Autodesk Fusion 360 part; units mm, degrees
(part 4 of 7)
sketch "Rear slot mouth sketch (2)" plane through (0, 0, 35) normal (0, 0, 1) x (1, 0, 0) in component "Vertical rail 1 - nominal 2020 slot-6 envelope"
  line L0 (117, 2) -> (123, 2)
  line L1 (123, 2) -> (123, 238)
  line L2 (123, 238) -> (117, 238)
  line L3 (117, 238) -> (117, 2)
  dimension "d1401" = 117
  dimension "d1402" = 2
  dimension "d1403" = 6
  dimension "d1404" = 236
  constraint horizontal L0
  constraint vertical L1
  constraint horizontal L2
  constraint vertical L3
  measures "d1401" horizontal distance of origin L0.start
  measures "d1402" vertical distance of origin L0.start
  measures "d1403" horizontal distance of L0.start L0.end
  measures "d1404" vertical distance of L0.end L1.end
extrude "Rear slot mouth'" cut sketch "Rear slot mouth sketch (2)" against normal blind 1.8 bodies 10 in component "Vertical rail 1 - nominal 2020 slot-6 envelope"
ref_plane "WorkPlane5" through (0, 0, 33.2) normal (0, 0, 1) x (1, 0, 0) in component "Vertical rail 1 - nominal 2020 slot-6 envelope"
sketch "Rear T nut cavity sketch (2)" plane through (0, 0, 33.2) normal (0, 0, 1) x (1, 0, 0) in component "Vertical rail 1 - nominal 2020 slot-6 envelope"
  line L0 (115, 2) -> (125, 2)
  line L1 (125, 2) -> (125, 238)
  line L2 (125, 238) -> (115, 238)
  line L3 (115, 238) -> (115, 2)
  dimension "d1409" = 115
  dimension "d1410" = 2
  dimension "d1411" = 10
  dimension "d1412" = 236
  constraint horizontal L0
  constraint vertical L1
  constraint horizontal L2
  constraint vertical L3
  measures "d1409" horizontal distance of origin L0.start
  measures "d1410" vertical distance of origin L0.start
  measures "d1411" horizontal distance of L0.start L0.end
  measures "d1412" vertical distance of L0.end L1.end
extrude "Rear T nut cavity'" cut sketch "Rear T nut cavity sketch (2)" against normal blind 4.2 bodies 10 in component "Vertical rail 1 - nominal 2020 slot-6 envelope"
ref_plane "WorkPlane4" through (0, 0, 35) normal (0, 0, 1) x (1, 0, 0) in component "Vertical rail 2 - nominal 2020 slot-6 envelope"
sketch "Rear slot mouth sketch (3)" plane through (0, 0, 35) normal (0, 0, 1) x (1, 0, 0) in component "Vertical rail 2 - nominal 2020 slot-6 envelope"
  line L0 (225, 2) -> (231, 2)
  line L1 (231, 2) -> (231, 238)
  line L2 (231, 238) -> (225, 238)
  line L3 (225, 238) -> (225, 2)
  dimension "d1417" = 225
  dimension "d1418" = 2
  dimension "d1419" = 6
  dimension "d1420" = 236
  constraint horizontal L0
  constraint vertical L1
  constraint horizontal L2
  constraint vertical L3
  measures "d1417" horizontal distance of origin L0.start
  measures "d1418" vertical distance of origin L0.start
  measures "d1419" horizontal distance of L0.start L0.end
  measures "d1420" vertical distance of L0.end L1.end
extrude "Rear slot mouth''" cut sketch "Rear slot mouth sketch (3)" against normal blind 1.8 bodies 11 in component "Vertical rail 2 - nominal 2020 slot-6 envelope"
ref_plane "WorkPlane5" through (0, 0, 33.2) normal (0, 0, 1) x (1, 0, 0) in component "Vertical rail 2 - nominal 2020 slot-6 envelope"
sketch "Rear T nut cavity sketch (3)" plane through (0, 0, 33.2) normal (0, 0, 1) x (1, 0, 0) in component "Vertical rail 2 - nominal 2020 slot-6 envelope"
  line L0 (223, 2) -> (233, 2)
  line L1 (233, 2) -> (233, 238)
  line L2 (233, 238) -> (223, 238)
  line L3 (223, 238) -> (223, 2)
  dimension "d1425" = 223
  dimension "d1426" = 2
  dimension "d1427" = 10
  dimension "d1428" = 236
  constraint horizontal L0
  constraint vertical L1
  constraint horizontal L2
  constraint vertical L3
  measures "d1425" horizontal distance of origin L0.start
  measures "d1426" vertical distance of origin L0.start
  measures "d1427" horizontal distance of L0.start L0.end
  measures "d1428" vertical distance of L0.end L1.end
extrude "Rear T nut cavity''" cut sketch "Rear T nut cavity sketch (3)" against normal blind 4.2 bodies 11 in component "Vertical rail 2 - nominal 2020 slot-6 envelope"
ref_plane "WorkPlane4" through (0, 0, 35) normal (0, 0, 1) x (1, 0, 0) in component "Horizontal tie 00 - nominal 2020 slot-6 envelope"
sketch "Rear slot mouth sketch (4)" plane through (0, 0, 35) normal (0, 0, 1) x (1, 0, 0) in component "Horizontal tie 00 - nominal 2020 slot-6 envelope"
  line L0 (22, 9) -> (110, 9)
  line L1 (110, 9) -> (110, 15)
  line L2 (110, 15) -> (22, 15)
  line L3 (22, 15) -> (22, 9)
  dimension "d1433" = 22
  dimension "d1434" = 9
  dimension "d1435" = 88
  dimension "d1436" = 6
  constraint horizontal L0
  constraint vertical L1
  constraint horizontal L2
  constraint vertical L3
  measures "d1433" horizontal distance of origin L0.start
  measures "d1434" vertical distance of origin L0.start
  measures "d1435" horizontal distance of L0.start L0.end
  measures "d1436" vertical distance of L0.end L1.end
extrude "Rear slot mouth'''" cut sketch "Rear slot mouth sketch (4)" against normal blind 1.8 bodies 12 in component "Horizontal tie 00 - nominal 2020 slot-6 envelope"
ref_plane "WorkPlane5" through (0, 0, 33.2) normal (0, 0, 1) x (1, 0, 0) in component "Horizontal tie 00 - nominal 2020 slot-6 envelope"
sketch "Rear T nut cavity sketch (4)" plane through (0, 0, 33.2) normal (0, 0, 1) x (1, 0, 0) in component "Horizontal tie 00 - nominal 2020 slot-6 envelope"
  line L0 (22, 7) -> (110, 7)
  line L1 (110, 7) -> (110, 17)
  line L2 (110, 17) -> (22, 17)
  line L3 (22, 17) -> (22, 7)
  dimension "d1441" = 22
  dimension "d1442" = 7
  dimension "d1443" = 88
  dimension "d1444" = 10
  constraint horizontal L0
  constraint vertical L1
  constraint horizontal L2
  constraint vertical L3
  measures "d1441" horizontal distance of origin L0.start
  measures "d1442" vertical distance of origin L0.start
  measures "d1443" horizontal distance of L0.start L0.end
  measures "d1444" vertical distance of L0.end L1.end
extrude "Rear T nut cavity'''" cut sketch "Rear T nut cavity sketch (4)" against normal blind 4.2 bodies 12 in component "Horizontal tie 00 - nominal 2020 slot-6 envelope"
ref_plane "WorkPlane4" through (0, 0, 35) normal (0, 0, 1) x (1, 0, 0) in component "Horizontal tie 10 - nominal 2020 slot-6 envelope"
sketch "Rear slot mouth sketch (5)" plane through (0, 0, 35) normal (0, 0, 1) x (1, 0, 0) in component "Horizontal tie 10 - nominal 2020 slot-6 envelope"
  line L0 (130, 9) -> (218, 9)
  line L1 (218, 9) -> (218, 15)
  line L2 (218, 15) -> (130, 15)
  line L3 (130, 15) -> (130, 9)
  dimension "d1449" = 130
  dimension "d1450" = 9
  dimension "d1451" = 88
  dimension "d1452" = 6
  constraint horizontal L0
  constraint vertical L1
  constraint horizontal L2
  constraint vertical L3
  measures "d1449" horizontal distance of origin L0.start
  measures "d1450" vertical distance of origin L0.start
  measures "d1451" horizontal distance of L0.start L0.end
  measures "d1452" vertical distance of L0.end L1.end
extrude "Rear slot mouth''''" cut sketch "Rear slot mouth sketch (5)" against normal blind 1.8 bodies 13 in component "Horizontal tie 10 - nominal 2020 slot-6 envelope"
ref_plane "WorkPlane5" through (0, 0, 33.2) normal (0, 0, 1) x (1, 0, 0) in component "Horizontal tie 10 - nominal 2020 slot-6 envelope"
sketch "Rear T nut cavity sketch (5)" plane through (0, 0, 33.2) normal (0, 0, 1) x (1, 0, 0) in component "Horizontal tie 10 - nominal 2020 slot-6 envelope"
  line L0 (130, 7) -> (218, 7)
  line L1 (218, 7) -> (218, 17)
  line L2 (218, 17) -> (130, 17)
  line L3 (130, 17) -> (130, 7)
  dimension "d1457" = 130
  dimension "d1458" = 7
  dimension "d1459" = 88
  dimension "d1460" = 10
  constraint horizontal L0
  constraint vertical L1
  constraint horizontal L2
  constraint vertical L3
  measures "d1457" horizontal distance of origin L0.start
  measures "d1458" vertical distance of origin L0.start
  measures "d1459" horizontal distance of L0.start L0.end
  measures "d1460" vertical distance of L0.end L1.end
extrude "Rear T nut cavity''''" cut sketch "Rear T nut cavity sketch (5)" against normal blind 4.2 bodies 13 in component "Horizontal tie 10 - nominal 2020 slot-6 envelope"
ref_plane "WorkPlane1" through (0, 0, 35) normal (0, 0, 1) x (1, 0, 0) in component "METAL rear splice plate 00"
sketch "Rear rail join plate sketch" plane through (0, 0, 35) normal (0, 0, 1) x (1, 0, 0) in component "METAL rear splice plate 00"
  line L0 (4, 4) -> (40, 4)
  line L1 (40, 4) -> (40, 20)
  line L2 (40, 20) -> (4, 20)
  line L3 (4, 20) -> (4, 4)
  dimension "d1465" = 4
  dimension "d1466" = 4
  dimension "d1467" = 36
  dimension "d1468" = 16
  constraint horizontal L0
  constraint vertical L1
  constraint horizontal L2
  constraint vertical L3
  measures "d1465" horizontal distance of origin L0.start
  measures "d1466" vertical distance of origin L0.start
  measures "d1467" horizontal distance of L0.start L0.end
  measures "d1468" vertical distance of L0.end L1.end
extrude "Rear rail join plate" add sketch "Rear rail join plate sketch" along normal blind 3 separate body makes body 61 in component "METAL rear splice plate 00"
ref_plane "WorkPlane2" through (0, 0, 35) normal (0, 0, 1) x (1, 0, 0) in component "METAL rear splice plate 00"
sketch "M5 clearance sketch (10)" plane through (0, 0, 35) normal (0, 0, 1) x (1, 0, 0) in component "METAL rear splice plate 00"
  circle A0 centre (12, 12) radius 2.75
  dimension "d1473" = 12
  dimension "d1474" = 12
  dimension "d1475" = 5.5
  measures "d1473" horizontal distance of origin A0.centre
  measures "d1474" vertical distance of origin A0.centre
  measures "d1475" diameter of A0
extrude "M5 clearance'''''''''" cut sketch "M5 clearance sketch (10)" along normal blind 3 bodies 61 in component "METAL rear splice plate 00"
ref_plane "WorkPlane1" through (0, 0, 38) normal (0, 0, 1) x (1, 0, 0) in component "REFERENCE rear join screw 000"
sketch "Nominal head sketch" plane through (0, 0, 38) normal (0, 0, 1) x (1, 0, 0) in component "REFERENCE rear join screw 000"
  circle A0 centre (12, 12) radius 4.75
  dimension "d1480" = 12
  dimension "d1481" = 12
  dimension "d1482" = 9.5
  measures "d1480" horizontal distance of origin A0.centre
  measures "d1481" vertical distance of origin A0.centre
  measures "d1482" diameter of A0
extrude "Nominal head" add sketch "Nominal head sketch" along normal blind 3 separate body makes body 62 in component "REFERENCE rear join screw 000"
ref_plane "WorkPlane2" through (0, 0, 38) normal (0, 0, 1) x (1, 0, 0) in component "REFERENCE rear join screw 000"
sketch "M5x8 nominal shank sketch" plane through (0, 0, 38) normal (0, 0, 1) x (1, 0, 0) in component "REFERENCE rear join screw 000"
  circle A0 centre (12, 12) radius 2.5
  dimension "d1487" = 12
  dimension "d1488" = 12
  dimension "d1489" = 5
  measures "d1487" horizontal distance of origin A0.centre
  measures "d1488" vertical distance of origin A0.centre
  measures "d1489" diameter of A0
extrude "M5x8 nominal shank" add sketch "M5x8 nominal shank sketch" against normal blind 8 bodies 62 in component "REFERENCE rear join screw 000"
ref_plane "WorkPlane1" through (0, 0, 29) normal (0, 0, 1) x (1, 0, 0) in component "REFERENCE rear T nut 000"
sketch "T nut envelope sketch (10)" plane through (0, 0, 29) normal (0, 0, 1) x (1, 0, 0) in component "REFERENCE rear T nut 000"
  line L0 (7.2, 7.2) -> (16.8, 7.2)
  line L1 (16.8, 7.2) -> (16.8, 16.8)
  line L2 (16.8, 16.8) -> (7.2, 16.8)
  line L3 (7.2, 16.8) -> (7.2, 7.2)
  dimension "d1494" = 7.2
  dimension "d1495" = 7.2
  dimension "d1496" = 9.6
  dimension "d1497" = 9.6
  constraint horizontal L0
  constraint vertical L1
  constraint horizontal L2
  constraint vertical L3
  measures "d1494" horizontal distance of origin L0.start
  measures "d1495" vertical distance of origin L0.start
  measures "d1496" horizontal distance of L0.start L0.end
  measures "d1497" vertical distance of L0.end L1.end
extrude "T nut envelope'''''''''" add sketch "T nut envelope sketch (10)" along normal blind 4 separate body makes body 63 in component "REFERENCE rear T nut 000"
ref_plane "WorkPlane2" through (0, 0, 29) normal (0, 0, 1) x (1, 0, 0) in component "REFERENCE rear T nut 000"
sketch "Thread envelope sketch (10)" plane through (0, 0, 29) normal (0, 0, 1) x (1, 0, 0) in component "REFERENCE rear T nut 000"
  circle A0 centre (12, 12) radius 2.6
  dimension "d1502" = 12
  dimension "d1503" = 12
  dimension "d1504" = 5.2
  measures "d1502" horizontal distance of origin A0.centre
  measures "d1503" vertical distance of origin A0.centre
  measures "d1504" diameter of A0
extrude "Thread envelope'''''''''" cut sketch "Thread envelope sketch (10)" along normal blind 4 bodies 62 in component "REFERENCE rear join screw 000"
extrude "Extrude2'''''''''" cut sketch "Thread envelope sketch (10)" along normal blind 4 bodies 63 in component "REFERENCE rear T nut 000"
ref_plane "WorkPlane3" through (0, 0, 35) normal (0, 0, 1) x (1, 0, 0) in component "METAL rear splice plate 00"
sketch "M5 clearance sketch (1)" plane through (0, 0, 35) normal (0, 0, 1) x (1, 0, 0) in component "METAL rear splice plate 00"
  circle A0 centre (32, 12) radius 2.75
  dimension "d1511" = 32
  dimension "d1512" = 12
  dimension "d1513" = 5.5
  measures "d1511" horizontal distance of origin A0.centre
  measures "d1512" vertical distance of origin A0.centre
  measures "d1513" diameter of A0
extrude "M5 clearance (1)" cut sketch "M5 clearance sketch (1)" along normal blind 3 bodies 61 in component "METAL rear splice plate 00"
ref_plane "WorkPlane1" through (0, 0, 38) normal (0, 0, 1) x (1, 0, 0) in component "REFERENCE rear join screw 001"
sketch "Nominal head sketch (2)" plane through (0, 0, 38) normal (0, 0, 1) x (1, 0, 0) in component "REFERENCE rear join screw 001"
  circle A0 centre (32, 12) radius 4.75
  dimension "d1518" = 32
  dimension "d1519" = 12
  dimension "d1520" = 9.5
  measures "d1518" horizontal distance of origin A0.centre
  measures "d1519" vertical distance of origin A0.centre
  measures "d1520" diameter of A0
extrude "Nominal head'" add sketch "Nominal head sketch (2)" along normal blind 3 separate body makes body 64 in component "REFERENCE rear join screw 001"
ref_plane "WorkPlane2" through (0, 0, 38) normal (0, 0, 1) x (1, 0, 0) in component "REFERENCE rear join screw 001"
sketch "M5x8 nominal shank sketch (2)" plane through (0, 0, 38) normal (0, 0, 1) x (1, 0, 0) in component "REFERENCE rear join screw 001"
  circle A0 centre (32, 12) radius 2.5
  dimension "d1525" = 32
  dimension "d1526" = 12
  dimension "d1527" = 5
  measures "d1525" horizontal distance of origin A0.centre
  measures "d1526" vertical distance of origin A0.centre
  measures "d1527" diameter of A0
extrude "M5x8 nominal shank'" add sketch "M5x8 nominal shank sketch (2)" against normal blind 8 bodies 64 in component "REFERENCE rear join screw 001"
ref_plane "WorkPlane1" through (0, 0, 29) normal (0, 0, 1) x (1, 0, 0) in component "REFERENCE rear T nut 001"
sketch "T nut envelope sketch (11)" plane through (0, 0, 29) normal (0, 0, 1) x (1, 0, 0) in component "REFERENCE rear T nut 001"
  line L0 (27.2, 7.2) -> (36.8, 7.2)
  line L1 (36.8, 7.2) -> (36.8, 16.8)
  line L2 (36.8, 16.8) -> (27.2, 16.8)
  line L3 (27.2, 16.8) -> (27.2, 7.2)
  dimension "d1532" = 27.2
  dimension "d1533" = 7.2
  dimension "d1534" = 9.6
  dimension "d1535" = 9.6
  constraint horizontal L0
  constraint vertical L1
  constraint horizontal L2
  constraint vertical L3
  measures "d1532" horizontal distance of origin L0.start
  measures "d1533" vertical distance of origin L0.start
  measures "d1534" horizontal distance of L0.start L0.end
  measures "d1535" vertical distance of L0.end L1.end
extrude "T nut envelope''''''''''" add sketch "T nut envelope sketch (11)" along normal blind 4 separate body makes body 65 in component "REFERENCE rear T nut 001"
ref_plane "WorkPlane2" through (0, 0, 29) normal (0, 0, 1) x (1, 0, 0) in component "REFERENCE rear T nut 001"
sketch "Thread envelope sketch (11)" plane through (0, 0, 29) normal (0, 0, 1) x (1, 0, 0) in component "REFERENCE rear T nut 001"
  circle A0 centre (32, 12) radius 2.6
  dimension "d1540" = 32
  dimension "d1541" = 12
  dimension "d1542" = 5.2
  measures "d1540" horizontal distance of origin A0.centre
  measures "d1541" vertical distance of origin A0.centre
  measures "d1542" diameter of A0
extrude "Thread envelope''''''''''" cut sketch "Thread envelope sketch (11)" along normal blind 4 bodies 64 in component "REFERENCE rear join screw 001"
extrude "Extrude2''''''''''" cut sketch "Thread envelope sketch (11)" along normal blind 4 bodies 65 in component "REFERENCE rear T nut 001"
ref_plane "WorkPlane1" through (0, 0, 35) normal (0, 0, 1) x (1, 0, 0) in component "METAL rear splice plate 10"
sketch "Rear rail join plate sketch (2)" plane through (0, 0, 35) normal (0, 0, 1) x (1, 0, 0) in component "METAL rear splice plate 10"
  line L0 (92, 4) -> (148, 4)
  line L1 (148, 4) -> (148, 20)
  line L2 (148, 20) -> (92, 20)
  line L3 (92, 20) -> (92, 4)
  dimension "d1549" = 92
  dimension "d1550" = 4
  dimension "d1551" = 56
  dimension "d1552" = 16
  constraint horizontal L0
  constraint vertical L1
  constraint horizontal L2
  constraint vertical L3
  measures "d1549" horizontal distance of origin L0.start
  measures "d1550" vertical distance of origin L0.start
  measures "d1551" horizontal distance of L0.start L0.end
  measures "d1552" vertical distance of L0.end L1.end
extrude "Rear rail join plate'" add sketch "Rear rail join plate sketch (2)" along normal blind 3 separate body makes body 66 in component "METAL rear splice plate 10"
ref_plane "WorkPlane2" through (0, 0, 35) normal (0, 0, 1) x (1, 0, 0) in component "METAL rear splice plate 10"
sketch "M5 clearance sketch (11)" plane through (0, 0, 35) normal (0, 0, 1) x (1, 0, 0) in component "METAL rear splice plate 10"
  circle A0 centre (100, 12) radius 2.75
  dimension "d1557" = 100
  dimension "d1558" = 12
  dimension "d1559" = 5.5
  measures "d1557" horizontal distance of origin A0.centre
  measures "d1558" vertical distance of origin A0.centre
  measures "d1559" diameter of A0
extrude "M5 clearance''''''''''" cut sketch "M5 clearance sketch (11)" along normal blind 3 bodies 66 in component "METAL rear splice plate 10"
ref_plane "WorkPlane1" through (0, 0, 38) normal (0, 0, 1) x (1, 0, 0) in component "REFERENCE rear join screw 100"
sketch "Nominal head sketch (3)" plane through (0, 0, 38) normal (0, 0, 1) x (1, 0, 0) in component "REFERENCE rear join screw 100"
  circle A0 centre (100, 12) radius 4.75
  dimension "d1564" = 100
  dimension "d1565" = 12
  dimension "d1566" = 9.5
  measures "d1564" horizontal distance of origin A0.centre
  measures "d1565" vertical distance of origin A0.centre
  measures "d1566" diameter of A0
extrude "Nominal head''" add sketch "Nominal head sketch (3)" along normal blind 3 separate body makes body 67 in component "REFERENCE rear join screw 100"
ref_plane "WorkPlane2" through (0, 0, 38) normal (0, 0, 1) x (1, 0, 0) in component "REFERENCE rear join screw 100"
sketch "M5x8 nominal shank sketch (3)" plane through (0, 0, 38) normal (0, 0, 1) x (1, 0, 0) in component "REFERENCE rear join screw 100"
  circle A0 centre (100, 12) radius 2.5
  dimension "d1571" = 100
  dimension "d1572" = 12
  dimension "d1573" = 5
  measures "d1571" horizontal distance of origin A0.centre
  measures "d1572" vertical distance of origin A0.centre
  measures "d1573" diameter of A0
extrude "M5x8 nominal shank''" add sketch "M5x8 nominal shank sketch (3)" against normal blind 8 bodies 67 in component "REFERENCE rear join screw 100"
ref_plane "WorkPlane1" through (0, 0, 29) normal (0, 0, 1) x (1, 0, 0) in component "REFERENCE rear T nut 100"
sketch "T nut envelope sketch (12)" plane through (0, 0, 29) normal (0, 0, 1) x (1, 0, 0) in component "REFERENCE rear T nut 100"
  line L0 (95.2, 7.2) -> (104.8, 7.2)
  line L1 (104.8, 7.2) -> (104.8, 16.8)
  line L2 (104.8, 16.8) -> (95.2, 16.8)
  line L3 (95.2, 16.8) -> (95.2, 7.2)
  dimension "d1578" = 95.2
  dimension "d1579" = 7.2
  dimension "d1580" = 9.6
  dimension "d1581" = 9.6
  constraint horizontal L0
  constraint vertical L1
  constraint horizontal L2
  constraint vertical L3
  measures "d1578" horizontal distance of origin L0.start
  measures "d1579" vertical distance of origin L0.start
  measures "d1580" horizontal distance of L0.start L0.end
  measures "d1581" vertical distance of L0.end L1.end
extrude "T nut envelope'''''''''''" add sketch "T nut envelope sketch (12)" along normal blind 4 separate body makes body 68 in component "REFERENCE rear T nut 100"
ref_plane "WorkPlane2" through (0, 0, 29) normal (0, 0, 1) x (1, 0, 0) in component "REFERENCE rear T nut 100"
sketch "Thread envelope sketch (12)" plane through (0, 0, 29) normal (0, 0, 1) x (1, 0, 0) in component "REFERENCE rear T nut 100"
  circle A0 centre (100, 12) radius 2.6
  dimension "d1586" = 100
  dimension "d1587" = 12
  dimension "d1588" = 5.2
  measures "d1586" horizontal distance of origin A0.centre
  measures "d1587" vertical distance of origin A0.centre
  measures "d1588" diameter of A0
extrude "Thread envelope'''''''''''" cut sketch "Thread envelope sketch (12)" along normal blind 4 bodies 67 in component "REFERENCE rear join screw 100"
extrude "Extrude2'''''''''''" cut sketch "Thread envelope sketch (12)" along normal blind 4 bodies 68 in component "REFERENCE rear T nut 100"
ref_plane "WorkPlane3" through (0, 0, 35) normal (0, 0, 1) x (1, 0, 0) in component "METAL rear splice plate 10"
sketch "M5 clearance sketch (1) (2)" plane through (0, 0, 35) normal (0, 0, 1) x (1, 0, 0) in component "METAL rear splice plate 10"
  circle A0 centre (120, 12) radius 2.75
  dimension "d1595" = 120
  dimension "d1596" = 12
  dimension "d1597" = 5.5
  measures "d1595" horizontal distance of origin A0.centre
  measures "d1596" vertical distance of origin A0.centre
  measures "d1597" diameter of A0
extrude "M5 clearance (1)'" cut sketch "M5 clearance sketch (1) (2)" along normal blind 3 bodies 66 in component "METAL rear splice plate 10"
ref_plane "WorkPlane1" through (0, 0, 38) normal (0, 0, 1) x (1, 0, 0) in component "REFERENCE rear join screw 101"
sketch "Nominal head sketch (4)" plane through (0, 0, 38) normal (0, 0, 1) x (1, 0, 0) in component "REFERENCE rear join screw 101"
  circle A0 centre (120, 12) radius 4.75
  dimension "d1602" = 120
  dimension "d1603" = 12
  dimension "d1604" = 9.5
  measures "d1602" horizontal distance of origin A0.centre
  measures "d1603" vertical distance of origin A0.centre
  measures "d1604" diameter of A0
extrude "Nominal head'''" add sketch "Nominal head sketch (4)" along normal blind 3 separate body makes body 69 in component "REFERENCE rear join screw 101"
ref_plane "WorkPlane2" through (0, 0, 38) normal (0, 0, 1) x (1, 0, 0) in component "REFERENCE rear join screw 101"
sketch "M5x8 nominal shank sketch (4)" plane through (0, 0, 38) normal (0, 0, 1) x (1, 0, 0) in component "REFERENCE rear join screw 101"
  circle A0 centre (120, 12) radius 2.5
  dimension "d1609" = 120
  dimension "d1610" = 12
  dimension "d1611" = 5
  measures "d1609" horizontal distance of origin A0.centre
  measures "d1610" vertical distance of origin A0.centre
  measures "d1611" diameter of A0
extrude "M5x8 nominal shank'''" add sketch "M5x8 nominal shank sketch (4)" against normal blind 8 bodies 69 in component "REFERENCE rear join screw 101"
ref_plane "WorkPlane1" through (0, 0, 29) normal (0, 0, 1) x (1, 0, 0) in component "REFERENCE rear T nut 101"
sketch "T nut envelope sketch (13)" plane through (0, 0, 29) normal (0, 0, 1) x (1, 0, 0) in component "REFERENCE rear T nut 101"
  line L0 (115.2, 7.2) -> (124.8, 7.2)
  line L1 (124.8, 7.2) -> (124.8, 16.8)
  line L2 (124.8, 16.8) -> (115.2, 16.8)
  line L3 (115.2, 16.8) -> (115.2, 7.2)
  dimension "d1616" = 115.2
  dimension "d1617" = 7.2
  dimension "d1618" = 9.6
  dimension "d1619" = 9.6
  constraint horizontal L0
  constraint vertical L1
  constraint horizontal L2
  constraint vertical L3
  measures "d1616" horizontal distance of origin L0.start
  measures "d1617" vertical distance of origin L0.start
  measures "d1618" horizontal distance of L0.start L0.end
  measures "d1619" vertical distance of L0.end L1.end
extrude "T nut envelope''''''''''''" add sketch "T nut envelope sketch (13)" along normal blind 4 separate body makes body 70 in component "REFERENCE rear T nut 101"
ref_plane "WorkPlane2" through (0, 0, 29) normal (0, 0, 1) x (1, 0, 0) in component "REFERENCE rear T nut 101"
sketch "Thread envelope sketch (13)" plane through (0, 0, 29) normal (0, 0, 1) x (1, 0, 0) in component "REFERENCE rear T nut 101"
  circle A0 centre (120, 12) radius 2.6
  dimension "d1624" = 120
  dimension "d1625" = 12
  dimension "d1626" = 5.2
  measures "d1624" horizontal distance of origin A0.centre
  measures "d1625" vertical distance of origin A0.centre
  measures "d1626" diameter of A0
extrude "Thread envelope''''''''''''" cut sketch "Thread envelope sketch (13)" along normal blind 4 bodies 69 in component "REFERENCE rear join screw 101"
extrude "Extrude2''''''''''''" cut sketch "Thread envelope sketch (13)" along normal blind 4 bodies 70 in component "REFERENCE rear T nut 101"
ref_plane "WorkPlane4" through (0, 0, 35) normal (0, 0, 1) x (1, 0, 0) in component "METAL rear splice plate 10"
sketch "M5 clearance sketch (2) (2)" plane through (0, 0, 35) normal (0, 0, 1) x (1, 0, 0) in component "METAL rear splice plate 10"
  circle A0 centre (140, 12) radius 2.75
  dimension "d1633" = 140
  dimension "d1634" = 12
  dimension "d1635" = 5.5
  measures "d1633" horizontal distance of origin A0.centre
  measures "d1634" vertical distance of origin A0.centre
  measures "d1635" diameter of A0
extrude "M5 clearance (2)" cut sketch "M5 clearance sketch (2) (2)" along normal blind 3 bodies 66 in component "METAL rear splice plate 10"
ref_plane "WorkPlane1" through (0, 0, 38) normal (0, 0, 1) x (1, 0, 0) in component "REFERENCE rear join screw 102"
sketch "Nominal head sketch (5)" plane through (0, 0, 38) normal (0, 0, 1) x (1, 0, 0) in component "REFERENCE rear join screw 102"
  circle A0 centre (140, 12) radius 4.75
  dimension "d1640" = 140
  dimension "d1641" = 12
  dimension "d1642" = 9.5
  measures "d1640" horizontal distance of origin A0.centre
  measures "d1641" vertical distance of origin A0.centre
  measures "d1642" diameter of A0
extrude "Nominal head''''" add sketch "Nominal head sketch (5)" along normal blind 3 separate body makes body 71 in component "REFERENCE rear join screw 102"
ref_plane "WorkPlane2" through (0, 0, 38) normal (0, 0, 1) x (1, 0, 0) in component "REFERENCE rear join screw 102"
sketch "M5x8 nominal shank sketch (5)" plane through (0, 0, 38) normal (0, 0, 1) x (1, 0, 0) in component "REFERENCE rear join screw 102"
  circle A0 centre (140, 12) radius 2.5
  dimension "d1647" = 140
  dimension "d1648" = 12
  dimension "d1649" = 5
  measures "d1647" horizontal distance of origin A0.centre
  measures "d1648" vertical distance of origin A0.centre
  measures "d1649" diameter of A0
extrude "M5x8 nominal shank''''" add sketch "M5x8 nominal shank sketch (5)" against normal blind 8 bodies 71 in component "REFERENCE rear join screw 102"
ref_plane "WorkPlane1" through (0, 0, 29) normal (0, 0, 1) x (1, 0, 0) in component "REFERENCE rear T nut 102"
sketch "T nut envelope sketch (14)" plane through (0, 0, 29) normal (0, 0, 1) x (1, 0, 0) in component "REFERENCE rear T nut 102"
  line L0 (135.2, 7.2) -> (144.8, 7.2)
  line L1 (144.8, 7.2) -> (144.8, 16.8)
  line L2 (144.8, 16.8) -> (135.2, 16.8)
  line L3 (135.2, 16.8) -> (135.2, 7.2)
  dimension "d1654" = 135.2
  dimension "d1655" = 7.2
  dimension "d1656" = 9.6
  dimension "d1657" = 9.6
  constraint horizontal L0
  constraint vertical L1
  constraint horizontal L2
  constraint vertical L3
  measures "d1654" horizontal distance of origin L0.start
  measures "d1655" vertical distance of origin L0.start
  measures "d1656" horizontal distance of L0.start L0.end
  measures "d1657" vertical distance of L0.end L1.end
extrude "T nut envelope'''''''''''''" add sketch "T nut envelope sketch (14)" along normal blind 4 separate body makes body 72 in component "REFERENCE rear T nut 102"
ref_plane "WorkPlane2" through (0, 0, 29) normal (0, 0, 1) x (1, 0, 0) in component "REFERENCE rear T nut 102"
sketch "Thread envelope sketch (14)" plane through (0, 0, 29) normal (0, 0, 1) x (1, 0, 0) in component "REFERENCE rear T nut 102"
  circle A0 centre (140, 12) radius 2.6
  dimension "d1662" = 140
  dimension "d1663" = 12
  dimension "d1664" = 5.2
  measures "d1662" horizontal distance of origin A0.centre
  measures "d1663" vertical distance of origin A0.centre
  measures "d1664" diameter of A0
extrude "Thread envelope'''''''''''''" cut sketch "Thread envelope sketch (14)" along normal blind 4 bodies 71 in component "REFERENCE rear join screw 102"
extrude "Extrude2'''''''''''''" cut sketch "Thread envelope sketch (14)" along normal blind 4 bodies 72 in component "REFERENCE rear T nut 102"
ref_plane "WorkPlane1" through (0, 0, 35) normal (0, 0, 1) x (1, 0, 0) in component "METAL rear splice plate 20"
sketch "Rear rail join plate sketch (3)" plane through (0, 0, 35) normal (0, 0, 1) x (1, 0, 0) in component "METAL rear splice plate 20"
  line L0 (200, 4) -> (236, 4)
  line L1 (236, 4) -> (236, 20)
  line L2 (236, 20) -> (200, 20)
  line L3 (200, 20) -> (200, 4)
  dimension "d1671" = 200
  dimension "d1672" = 4
  dimension "d1673" = 36
  dimension "d1674" = 16
  constraint horizontal L0
  constraint vertical L1
  constraint horizontal L2
  constraint vertical L3
  measures "d1671" horizontal distance of origin L0.start
  measures "d1672" vertical distance of origin L0.start
  measures "d1673" horizontal distance of L0.start L0.end
  measures "d1674" vertical distance of L0.end L1.end
extrude "Rear rail join plate''" add sketch "Rear rail join plate sketch (3)" along normal blind 3 separate body makes body 73 in component "METAL rear splice plate 20"
ref_plane "WorkPlane2" through (0, 0, 35) normal (0, 0, 1) x (1, 0, 0) in component "METAL rear splice plate 20"
sketch "M5 clearance sketch (12)" plane through (0, 0, 35) normal (0, 0, 1) x (1, 0, 0) in component "METAL rear splice plate 20"
  circle A0 centre (208, 12) radius 2.75
  dimension "d1679" = 208
  dimension "d1680" = 12
  dimension "d1681" = 5.5
  measures "d1679" horizontal distance of origin A0.centre
  measures "d1680" vertical distance of origin A0.centre
  measures "d1681" diameter of A0
extrude "M5 clearance'''''''''''" cut sketch "M5 clearance sketch (12)" along normal blind 3 bodies 73 in component "METAL rear splice plate 20"
ref_plane "WorkPlane1" through (0, 0, 38) normal (0, 0, 1) x (1, 0, 0) in component "REFERENCE rear join screw 200"
sketch "Nominal head sketch (6)" plane through (0, 0, 38) normal (0, 0, 1) x (1, 0, 0) in component "REFERENCE rear join screw 200"
  circle A0 centre (208, 12) radius 4.75
  dimension "d1686" = 208
  dimension "d1687" = 12
  dimension "d1688" = 9.5
  measures "d1686" horizontal distance of origin A0.centre
  measures "d1687" vertical distance of origin A0.centre
  measures "d1688" diameter of A0
extrude "Nominal head'''''" add sketch "Nominal head sketch (6)" along normal blind 3 separate body makes body 74 in component "REFERENCE rear join screw 200"
ref_plane "WorkPlane2" through (0, 0, 38) normal (0, 0, 1) x (1, 0, 0) in component "REFERENCE rear join screw 200"
sketch "M5x8 nominal shank sketch (6)" plane through (0, 0, 38) normal (0, 0, 1) x (1, 0, 0) in component "REFERENCE rear join screw 200"
  circle A0 centre (208, 12) radius 2.5
  dimension "d1693" = 208
  dimension "d1694" = 12
  dimension "d1695" = 5
  measures "d1693" horizontal distance of origin A0.centre
  measures "d1694" vertical distance of origin A0.centre
  measures "d1695" diameter of A0
extrude "M5x8 nominal shank'''''" add sketch "M5x8 nominal shank sketch (6)" against normal blind 8 bodies 74 in component "REFERENCE rear join screw 200"
ref_plane "WorkPlane1" through (0, 0, 29) normal (0, 0, 1) x (1, 0, 0) in component "REFERENCE rear T nut 200"
sketch "T nut envelope sketch (15)" plane through (0, 0, 29) normal (0, 0, 1) x (1, 0, 0) in component "REFERENCE rear T nut 200"
  line L0 (203.2, 7.2) -> (212.8, 7.2)
  line L1 (212.8, 7.2) -> (212.8, 16.8)
  line L2 (212.8, 16.8) -> (203.2, 16.8)
  line L3 (203.2, 16.8) -> (203.2, 7.2)
  dimension "d1700" = 203.2
  dimension "d1701" = 7.2
  dimension "d1702" = 9.6
  dimension "d1703" = 9.6
  constraint horizontal L0
  constraint vertical L1
  constraint horizontal L2
  constraint vertical L3
  measures "d1700" horizontal distance of origin L0.start
  measures "d1701" vertical distance of origin L0.start
  measures "d1702" horizontal distance of L0.start L0.end
  measures "d1703" vertical distance of L0.end L1.end
extrude "T nut envelope''''''''''''''" add sketch "T nut envelope sketch (15)" along normal blind 4 separate body makes body 75 in component "REFERENCE rear T nut 200"
ref_plane "WorkPlane2" through (0, 0, 29) normal (0, 0, 1) x (1, 0, 0) in component "REFERENCE rear T nut 200"
sketch "Thread envelope sketch (15)" plane through (0, 0, 29) normal (0, 0, 1) x (1, 0, 0) in component "REFERENCE rear T nut 200"
  circle A0 centre (208, 12) radius 2.6
  dimension "d1708" = 208
  dimension "d1709" = 12
  dimension "d1710" = 5.2
  measures "d1708" horizontal distance of origin A0.centre
  measures "d1709" vertical distance of origin A0.centre
  measures "d1710" diameter of A0
extrude "Thread envelope''''''''''''''" cut sketch "Thread envelope sketch (15)" along normal blind 4 bodies 74 in component "REFERENCE rear join screw 200"
extrude "Extrude2''''''''''''''" cut sketch "Thread envelope sketch (15)" along normal blind 4 bodies 75 in component "REFERENCE rear T nut 200"
ref_plane "WorkPlane3" through (0, 0, 35) normal (0, 0, 1) x (1, 0, 0) in component "METAL rear splice plate 20"
sketch "M5 clearance sketch (1) (3)" plane through (0, 0, 35) normal (0, 0, 1) x (1, 0, 0) in component "METAL rear splice plate 20"
  circle A0 centre (228, 12) radius 2.75
  dimension "d1717" = 228
  dimension "d1718" = 12
  dimension "d1719" = 5.5
  measures "d1717" horizontal distance of origin A0.centre
  measures "d1718" vertical distance of origin A0.centre
  measures "d1719" diameter of A0
extrude "M5 clearance (1)''" cut sketch "M5 clearance sketch (1) (3)" along normal blind 3 bodies 73 in component "METAL rear splice plate 20"
ref_plane "WorkPlane1" through (0, 0, 38) normal (0, 0, 1) x (1, 0, 0) in component "REFERENCE rear join screw 201"
sketch "Nominal head sketch (7)" plane through (0, 0, 38) normal (0, 0, 1) x (1, 0, 0) in component "REFERENCE rear join screw 201"
  circle A0 centre (228, 12) radius 4.75
  dimension "d1724" = 228
  dimension "d1725" = 12
  dimension "d1726" = 9.5
  measures "d1724" horizontal distance of origin A0.centre
  measures "d1725" vertical distance of origin A0.centre
  measures "d1726" diameter of A0
extrude "Nominal head''''''" add sketch "Nominal head sketch (7)" along normal blind 3 separate body makes body 76 in component "REFERENCE rear join screw 201"
ref_plane "WorkPlane2" through (0, 0, 38) normal (0, 0, 1) x (1, 0, 0) in component "REFERENCE rear join screw 201"
sketch "M5x8 nominal shank sketch (7)" plane through (0, 0, 38) normal (0, 0, 1) x (1, 0, 0) in component "REFERENCE rear join screw 201"
  circle A0 centre (228, 12) radius 2.5
  dimension "d1731" = 228
  dimension "d1732" = 12
  dimension "d1733" = 5
  measures "d1731" horizontal distance of origin A0.centre
  measures "d1732" vertical distance of origin A0.centre
  measures "d1733" diameter of A0
extrude "M5x8 nominal shank''''''" add sketch "M5x8 nominal shank sketch (7)" against normal blind 8 bodies 76 in component "REFERENCE rear join screw 201"
ref_plane "WorkPlane1" through (0, 0, 29) normal (0, 0, 1) x (1, 0, 0) in component "REFERENCE rear T nut 201"
sketch "T nut envelope sketch (16)" plane through (0, 0, 29) normal (0, 0, 1) x (1, 0, 0) in component "REFERENCE rear T nut 201"
  line L0 (223.2, 7.2) -> (232.8, 7.2)
  line L1 (232.8, 7.2) -> (232.8, 16.8)
  line L2 (232.8, 16.8) -> (223.2, 16.8)
  line L3 (223.2, 16.8) -> (223.2, 7.2)
  dimension "d1738" = 223.2
  dimension "d1739" = 7.2
  dimension "d1740" = 9.6
  dimension "d1741" = 9.6
  constraint horizontal L0
  constraint vertical L1
  constraint horizontal L2
  constraint vertical L3
  measures "d1738" horizontal distance of origin L0.start
  measures "d1739" vertical distance of origin L0.start
  measures "d1740" horizontal distance of L0.start L0.end
  measures "d1741" vertical distance of L0.end L1.end
extrude "T nut envelope'''''''''''''''" add sketch "T nut envelope sketch (16)" along normal blind 4 separate body makes body 77 in component "REFERENCE rear T nut 201"
ref_plane "WorkPlane2" through (0, 0, 29) normal (0, 0, 1) x (1, 0, 0) in component "REFERENCE rear T nut 201"
sketch "Thread envelope sketch (16)" plane through (0, 0, 29) normal (0, 0, 1) x (1, 0, 0) in component "REFERENCE rear T nut 201"
  circle A0 centre (228, 12) radius 2.6
  dimension "d1746" = 228
  dimension "d1747" = 12
  dimension "d1748" = 5.2
  measures "d1746" horizontal distance of origin A0.centre
  measures "d1747" vertical distance of origin A0.centre
  measures "d1748" diameter of A0
extrude "Thread envelope'''''''''''''''" cut sketch "Thread envelope sketch (16)" along normal blind 4 bodies 76 in component "REFERENCE rear join screw 201"
extrude "Extrude2'''''''''''''''" cut sketch "Thread envelope sketch (16)" along normal blind 4 bodies 77 in component "REFERENCE rear T nut 201"
ref_plane "WorkPlane4" through (0, 0, 35) normal (0, 0, 1) x (1, 0, 0) in component "Horizontal tie 01 - nominal 2020 slot-6 envelope"
sketch "Rear slot mouth sketch (6)" plane through (0, 0, 35) normal (0, 0, 1) x (1, 0, 0) in component "Horizontal tie 01 - nominal 2020 slot-6 envelope"
  line L0 (22, 225) -> (110, 225)
  line L1 (110, 225) -> (110, 231)
  line L2 (110, 231) -> (22, 231)
  line L3 (22, 231) -> (22, 225)
  dimension "d1755" = 22
  dimension "d1756" = 225
  dimension "d1757" = 88
  dimension "d1758" = 6
  constraint horizontal L0
  constraint vertical L1
  constraint horizontal L2
  constraint vertical L3
  measures "d1755" horizontal distance of origin L0.start
  measures "d1756" vertical distance of origin L0.start
  measures "d1757" horizontal distance of L0.start L0.end
  measures "d1758" vertical distance of L0.end L1.end
extrude "Rear slot mouth'''''" cut sketch "Rear slot mouth sketch (6)" against normal blind 1.8 bodies 14 in component "Horizontal tie 01 - nominal 2020 slot-6 envelope"
ref_plane "WorkPlane5" through (0, 0, 33.2) normal (0, 0, 1) x (1, 0, 0) in component "Horizontal tie 01 - nominal 2020 slot-6 envelope"
sketch "Rear T nut cavity sketch (6)" plane through (0, 0, 33.2) normal (0, 0, 1) x (1, 0, 0) in component "Horizontal tie 01 - nominal 2020 slot-6 envelope"
  line L0 (22, 223) -> (110, 223)
  line L1 (110, 223) -> (110, 233)
  line L2 (110, 233) -> (22, 233)
  line L3 (22, 233) -> (22, 223)
  dimension "d1763" = 22
  dimension "d1764" = 223
  dimension "d1765" = 88
  dimension "d1766" = 10
  constraint horizontal L0
  constraint vertical L1
  constraint horizontal L2
  constraint vertical L3
  measures "d1763" horizontal distance of origin L0.start
  measures "d1764" vertical distance of origin L0.start
  measures "d1765" horizontal distance of L0.start L0.end
  measures "d1766" vertical distance of L0.end L1.end
extrude "Rear T nut cavity'''''" cut sketch "Rear T nut cavity sketch (6)" against normal blind 4.2 bodies 14 in component "Horizontal tie 01 - nominal 2020 slot-6 envelope"
ref_plane "WorkPlane4" through (0, 0, 35) normal (0, 0, 1) x (1, 0, 0) in component "Horizontal tie 11 - nominal 2020 slot-6 envelope"
sketch "Rear slot mouth sketch (7)" plane through (0, 0, 35) normal (0, 0, 1) x (1, 0, 0) in component "Horizontal tie 11 - nominal 2020 slot-6 envelope"
  line L0 (130, 225) -> (218, 225)
  line L1 (218, 225) -> (218, 231)
  line L2 (218, 231) -> (130, 231)
  line L3 (130, 231) -> (130, 225)
  dimension "d1771" = 130
  dimension "d1772" = 225
  dimension "d1773" = 88
  dimension "d1774" = 6
  constraint horizontal L0
  constraint vertical L1
  constraint horizontal L2
  constraint vertical L3
  measures "d1771" horizontal distance of origin L0.start
  measures "d1772" vertical distance of origin L0.start
  measures "d1773" horizontal distance of L0.start L0.end
  measures "d1774" vertical distance of L0.end L1.end
extrude "Rear slot mouth''''''" cut sketch "Rear slot mouth sketch (7)" against normal blind 1.8 bodies 15 in component "Horizontal tie 11 - nominal 2020 slot-6 envelope"
ref_plane "WorkPlane5" through (0, 0, 33.2) normal (0, 0, 1) x (1, 0, 0) in component "Horizontal tie 11 - nominal 2020 slot-6 envelope"
sketch "Rear T nut cavity sketch (7)" plane through (0, 0, 33.2) normal (0, 0, 1) x (1, 0, 0) in component "Horizontal tie 11 - nominal 2020 slot-6 envelope"
  line L0 (130, 223) -> (218, 223)
  line L1 (218, 223) -> (218, 233)
  line L2 (218, 233) -> (130, 233)
  line L3 (130, 233) -> (130, 223)
  dimension "d1779" = 130
  dimension "d1780" = 223
  dimension "d1781" = 88
  dimension "d1782" = 10
  constraint horizontal L0
  constraint vertical L1
  constraint horizontal L2
  constraint vertical L3
  measures "d1779" horizontal distance of origin L0.start
  measures "d1780" vertical distance of origin L0.start
  measures "d1781" horizontal distance of L0.start L0.end
  measures "d1782" vertical distance of L0.end L1.end
extrude "Rear T nut cavity''''''" cut sketch "Rear T nut cavity sketch (7)" against normal blind 4.2 bodies 15 in component "Horizontal tie 11 - nominal 2020 slot-6 envelope"
ref_plane "WorkPlane1" through (0, 0, 35) normal (0, 0, 1) x (1, 0, 0) in component "METAL rear splice plate 01"
sketch "Rear rail join plate sketch (4)" plane through (0, 0, 35) normal (0, 0, 1) x (1, 0, 0) in component "METAL rear splice plate 01"
  line L0 (4, 220) -> (40, 220)
  line L1 (40, 220) -> (40, 236)
  line L2 (40, 236) -> (4, 236)
  line L3 (4, 236) -> (4, 220)
  dimension "d1787" = 4
  dimension "d1788" = 220
  dimension "d1789" = 36
  dimension "d1790" = 16
  constraint horizontal L0
  constraint vertical L1
  constraint horizontal L2
  constraint vertical L3
  measures "d1787" horizontal distance of origin L0.start
  measures "d1788" vertical distance of origin L0.start
  measures "d1789" horizontal distance of L0.start L0.end
  measures "d1790" vertical distance of L0.end L1.end
extrude "Rear rail join plate'''" add sketch "Rear rail join plate sketch (4)" along normal blind 3 separate body makes body 78 in component "METAL rear splice plate 01"
ref_plane "WorkPlane2" through (0, 0, 35) normal (0, 0, 1) x (1, 0, 0) in component "METAL rear splice plate 01"
sketch "M5 clearance sketch (13)" plane through (0, 0, 35) normal (0, 0, 1) x (1, 0, 0) in component "METAL rear splice plate 01"
  circle A0 centre (12, 228) radius 2.75
  dimension "d1795" = 12
  dimension "d1796" = 228
  dimension "d1797" = 5.5
  measures "d1795" horizontal distance of origin A0.centre
  measures "d1796" vertical distance of origin A0.centre
  measures "d1797" diameter of A0
extrude "M5 clearance''''''''''''" cut sketch "M5 clearance sketch (13)" along normal blind 3 bodies 78 in component "METAL rear splice plate 01"
ref_plane "WorkPlane1" through (0, 0, 38) normal (0, 0, 1) x (1, 0, 0) in component "REFERENCE rear join screw 010"
sketch "Nominal head sketch (8)" plane through (0, 0, 38) normal (0, 0, 1) x (1, 0, 0) in component "REFERENCE rear join screw 010"
  circle A0 centre (12, 228) radius 4.75
  dimension "d1802" = 12
  dimension "d1803" = 228
  dimension "d1804" = 9.5
  measures "d1802" horizontal distance of origin A0.centre
  measures "d1803" vertical distance of origin A0.centre
  measures "d1804" diameter of A0
extrude "Nominal head'''''''" add sketch "Nominal head sketch (8)" along normal blind 3 separate body makes body 79 in component "REFERENCE rear join screw 010"
ref_plane "WorkPlane2" through (0, 0, 38) normal (0, 0, 1) x (1, 0, 0) in component "REFERENCE rear join screw 010"
sketch "M5x8 nominal shank sketch (8)" plane through (0, 0, 38) normal (0, 0, 1) x (1, 0, 0) in component "REFERENCE rear join screw 010"
  circle A0 centre (12, 228) radius 2.5
  dimension "d1809" = 12
  dimension "d1810" = 228
  dimension "d1811" = 5
  measures "d1809" horizontal distance of origin A0.centre
  measures "d1810" vertical distance of origin A0.centre
  measures "d1811" diameter of A0
extrude "M5x8 nominal shank'''''''" add sketch "M5x8 nominal shank sketch (8)" against normal blind 8 bodies 79 in component "REFERENCE rear join screw 010"
ref_plane "WorkPlane1" through (0, 0, 29) normal (0, 0, 1) x (1, 0, 0) in component "REFERENCE rear T nut 010"
sketch "T nut envelope sketch (17)" plane through (0, 0, 29) normal (0, 0, 1) x (1, 0, 0) in component "REFERENCE rear T nut 010"
  line L0 (7.2, 223.2) -> (16.8, 223.2)
  line L1 (16.8, 223.2) -> (16.8, 232.8)
  line L2 (16.8, 232.8) -> (7.2, 232.8)
  line L3 (7.2, 232.8) -> (7.2, 223.2)
  dimension "d1816" = 7.2
  dimension "d1817" = 223.2
  dimension "d1818" = 9.6
  dimension "d1819" = 9.6
  constraint horizontal L0
  constraint vertical L1
  constraint horizontal L2
  constraint vertical L3
  measures "d1816" horizontal distance of origin L0.start
  measures "d1817" vertical distance of origin L0.start
  measures "d1818" horizontal distance of L0.start L0.end
  measures "d1819" vertical distance of L0.end L1.end
extrude "T nut envelope''''''''''''''''" add sketch "T nut envelope sketch (17)" along normal blind 4 separate body makes body 80 in component "REFERENCE rear T nut 010"
ref_plane "WorkPlane2" through (0, 0, 29) normal (0, 0, 1) x (1, 0, 0) in component "REFERENCE rear T nut 010"
sketch "Thread envelope sketch (17)" plane through (0, 0, 29) normal (0, 0, 1) x (1, 0, 0) in component "REFERENCE rear T nut 010"
  circle A0 centre (12, 228) radius 2.6
  dimension "d1824" = 12
  dimension "d1825" = 228
  dimension "d1826" = 5.2
  measures "d1824" horizontal distance of origin A0.centre
  measures "d1825" vertical distance of origin A0.centre
  measures "d1826" diameter of A0
extrude "Thread envelope''''''''''''''''" cut sketch "Thread envelope sketch (17)" along normal blind 4 bodies 79 in component "REFERENCE rear join screw 010"
extrude "Extrude2''''''''''''''''" cut sketch "Thread envelope sketch (17)" along normal blind 4 bodies 80 in component "REFERENCE rear T nut 010"
ref_plane "WorkPlane3" through (0, 0, 35) normal (0, 0, 1) x (1, 0, 0) in component "METAL rear splice plate 01"
sketch "M5 clearance sketch (1) (4)" plane through (0, 0, 35) normal (0, 0, 1) x (1, 0, 0) in component "METAL rear splice plate 01"
  circle A0 centre (32, 228) radius 2.75
  dimension "d1833" = 32
  dimension "d1834" = 228
  dimension "d1835" = 5.5
  measures "d1833" horizontal distance of origin A0.centre
  measures "d1834" vertical distance of origin A0.centre
  measures "d1835" diameter of A0
extrude "M5 clearance (1)'''" cut sketch "M5 clearance sketch (1) (4)" along normal blind 3 bodies 78 in component "METAL rear splice plate 01"
ref_plane "WorkPlane1" through (0, 0, 38) normal (0, 0, 1) x (1, 0, 0) in component "REFERENCE rear join screw 011"
sketch "Nominal head sketch (9)" plane through (0, 0, 38) normal (0, 0, 1) x (1, 0, 0) in component "REFERENCE rear join screw 011"
  circle A0 centre (32, 228) radius 4.75
  dimension "d1840" = 32
  dimension "d1841" = 228
  dimension "d1842" = 9.5
  measures "d1840" horizontal distance of origin A0.centre
  measures "d1841" vertical distance of origin A0.centre
  measures "d1842" diameter of A0
extrude "Nominal head''''''''" add sketch "Nominal head sketch (9)" along normal blind 3 separate body makes body 81 in component "REFERENCE rear join screw 011"
ref_plane "WorkPlane2" through (0, 0, 38) normal (0, 0, 1) x (1, 0, 0) in component "REFERENCE rear join screw 011"
sketch "M5x8 nominal shank sketch (9)" plane through (0, 0, 38) normal (0, 0, 1) x (1, 0, 0) in component "REFERENCE rear join screw 011"
  circle A0 centre (32, 228) radius 2.5
  dimension "d1847" = 32
  dimension "d1848" = 228
  dimension "d1849" = 5
  measures "d1847" horizontal distance of origin A0.centre
  measures "d1848" vertical distance of origin A0.centre
  measures "d1849" diameter of A0
extrude "M5x8 nominal shank''''''''" add sketch "M5x8 nominal shank sketch (9)" against normal blind 8 bodies 81 in component "REFERENCE rear join screw 011"
ref_plane "WorkPlane1" through (0, 0, 29) normal (0, 0, 1) x (1, 0, 0) in component "REFERENCE rear T nut 011"
sketch "T nut envelope sketch (18)" plane through (0, 0, 29) normal (0, 0, 1) x (1, 0, 0) in component "REFERENCE rear T nut 011"
  line L0 (27.2, 223.2) -> (36.8, 223.2)
  line L1 (36.8, 223.2) -> (36.8, 232.8)
  line L2 (36.8, 232.8) -> (27.2, 232.8)
  line L3 (27.2, 232.8) -> (27.2, 223.2)
  dimension "d1854" = 27.2
  dimension "d1855" = 223.2
  dimension "d1856" = 9.6
  dimension "d1857" = 9.6
  constraint horizontal L0
  constraint vertical L1
  constraint horizontal L2
  constraint vertical L3
  measures "d1854" horizontal distance of origin L0.start
  measures "d1855" vertical distance of origin L0.start
  measures "d1856" horizontal distance of L0.start L0.end
  measures "d1857" vertical distance of L0.end L1.end
extrude "T nut envelope'''''''''''''''''" add sketch "T nut envelope sketch (18)" along normal blind 4 separate body makes body 82 in component "REFERENCE rear T nut 011"
ref_plane "WorkPlane2" through (0, 0, 29) normal (0, 0, 1) x (1, 0, 0) in component "REFERENCE rear T nut 011"